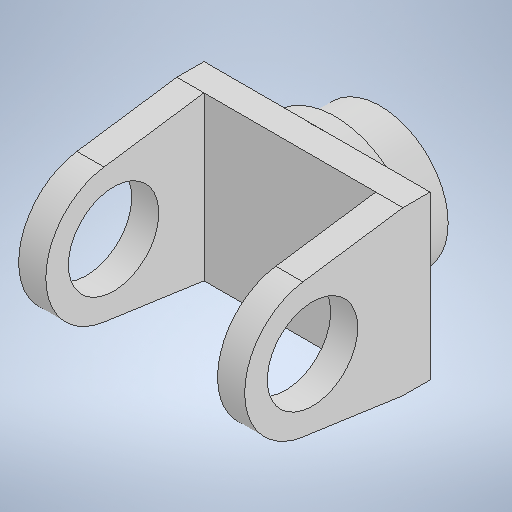
# Autodesk Inventor part: 3D_roter-mount
Saved by Autodesk Inventor 2025.3 (Build 293356030, 356C)
## iProperties
Created: 2026-01-04
Part Number: 3D_roter-mount
Material: 一般
Document SubType Name: Modeling
Designer: ibuki_ono
Density: 1 g/cm^3
Appearance: 既定
Author: ibuki_ono
Autodesk Inventor part; units mm, degrees
ref_plane "YZ Plane" through (0, 0, 0) normal (1, 0, 0) x (0, 1, 0)
ref_plane "XZ Plane" through (0, 0, 0) normal (0, 1, 0) x (-1, 0, 0)
ref_plane "XY Plane" through (0, 0, 0) normal (0, 0, 1) x (1, 0, 0)
sketch "スケッチ1" plane through (0, 0, 0) normal (0, 0, 1) x (1, 0, 0)
  circle A0 centre (0, 0) radius 7.5
  dimension "d0" = 15
  constraints: 1 centre point, 1 coincident
  measures "d0" diameter of A0
extrude "押し出し1" add sketch "スケッチ1" along normal blind 5
sketch "スケッチ2" plane through (0, 0, 5) normal (0, 0, 1) x (1, 0, 0)
  circle A0 centre (0, 0) radius 9
  dimension "d3" = 18
  constraints: 1 centre point, 1 coincident
  measures "d3" diameter of A0
extrude "押し出し2" add sketch "スケッチ2" along normal blind 2
sketch "スケッチ3" plane through (0, 0, 7) normal (0, 0, 1) x (1, 0, 0)
  circle A0 centre (0, 0) radius 9 projected
  line L0 (-12.5, -9) -> (12.5, -9)
  line L1 (12.5, -9) -> (12.5, 9)
  line L2 (12.5, 9) -> (-12.5, 9)
  line L3 (-12.5, 9) -> (-12.5, -9)
  line L4 (-12.5, -9) -> (12.5, 9) construction
  line L5 (12.5, -9) -> (-12.5, 9) construction
  circle A1 centre (0, 0) radius 9 projected
  dimension "d6" = 25
  constraints: 12 end point, 2 midpoint, 2 parallel, 1 horizontal, 1 perpendicular, 1 tangent
  measures "d6" distance of L1.end L2.end
extrude "押し出し3" add sketch "スケッチ3" along normal blind 3
sketch "スケッチ4" plane through (12.5, -9, 7) normal (1, 0, 0) x (0, 0, -1)
  line L0 (-3, 0) -> (-3, 18) projected
  circle A0 centre (-13, 9) radius 7.5
  line L1 (-14.0576, 16.4251) -> (-3, 18)
  line L2 (0, 0) -> (-3, 0) projected
  line L3 (-3, 0) -> (-14.0576, 1.5749)
  point P0 (7, 9)
  point P1 (-3, 9)
  dimension "d9" = 15
  dimension "d10" = 10
  constraints: 4 end point, 2 point on circle, 2 tangent, 1 centre point, 1 horizontal alignment, 1 midpoint
  measures "d9" diameter of A0
  measures "d10" distance from line of L0 A0.centre
extrude "押し出し4" add sketch "スケッチ4" against normal blind 3
sketch "スケッチ5" plane through (12.5, -9, 7) normal (1, 0, 0) x (0, 0, -1)
  arc A0 (-14.0576, 16.4251) -> (-14.0576, 1.5749) centre (-13, 9) ccw projected
  circle A1 centre (-13, 9) radius 5
  point P0 (7, 9)
  dimension "d13" = 10
  constraints: 1 centre point, 1 coincident
  measures "d13" diameter of A1
extrude "押し出し5" cut sketch "スケッチ5" against normal through all
mirror "ミラー1" about plane through (0, 0, 0) normal (1, 0, 0) of "押し出し4", "押し出し5"
